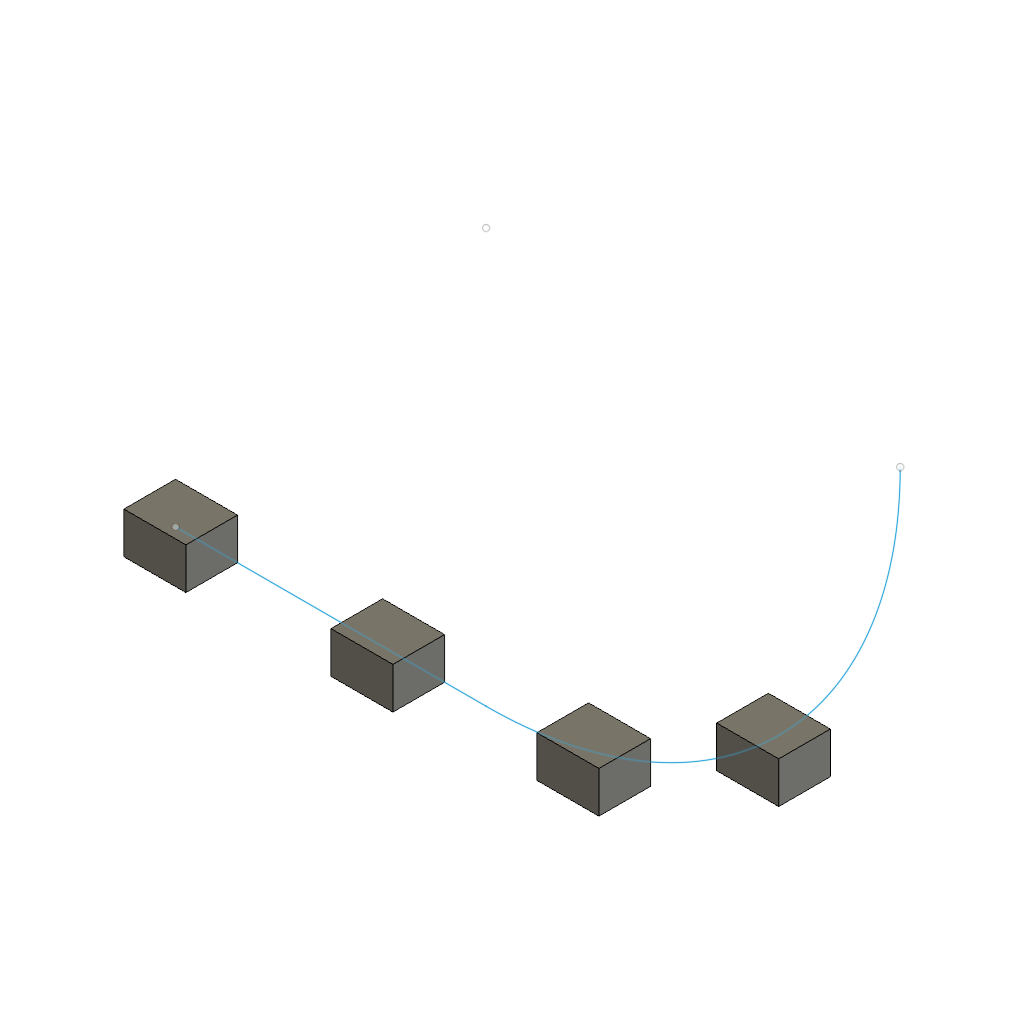
composite_identical (Autodesk Fusion 360 design; units mm, degrees)
part number: 2026-10-20-22-51-25-751
Autodesk Fusion 360 part; units mm, degrees
sketch "PatternSeedSketch0" plane through (0, 0, 0) normal (0, 0, 1) x (1, 0, 0)
  line L0 (0, 0) -> (6, 0)
  line L1 (6, 0) -> (6, 4)
  line L2 (6, 4) -> (0, 4)
  line L3 (0, 4) -> (0, 0)
extrude "PatternSeedFeature0" add sketch "PatternSeedSketch0" along normal blind 5 makes body 1
sketch "CompositePatternPath" plane through (0, 0, 0) normal (0, 0, 1) x (1, 0, 0)
  line L0 (0, 0) -> (30, 0)
  arc A0 (30, 0) -> (70, 40) centre (30, 40) ccw
pattern_path "ProbeCompositePathPattern" count 4 spacing 20 from (0, 0, 0) path "CompositePatternPath" along L0 A0 of bodies 1 makes body 2 at (24, 4, 1.6667) makes body 3 at (43.8962, 5.2435, 1.6667) makes body 4 at (61.2656, 14.7324, 1.6667)
named bodies: "PatternSeedBody0", "PatternSeedBody0 (1)", "PatternSeedBody0 (2)", "PatternSeedBody0 (3)"
